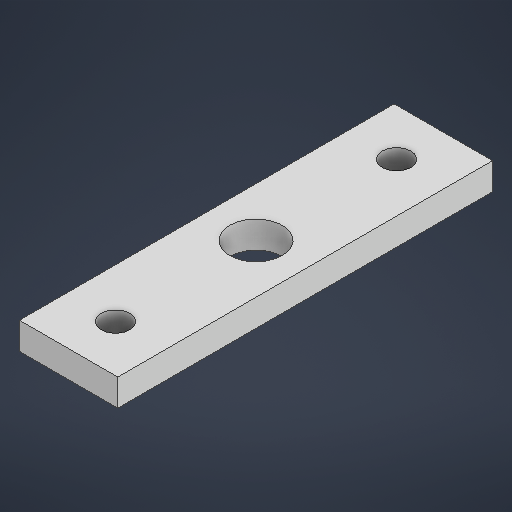
# Autodesk Inventor part: motor_hider_housing
Saved by Autodesk Inventor 2027.1 (Build 311270010, 270A)
## iProperties
Created: 2026-10-04
Part Number: motor_hider_housing
Material: Generic
Document SubType Name: Modeling
Designer: khaar
Density: 1 g/cm^3
Appearance: Default
Author: khaar
Autodesk Inventor part; units mm, degrees
ref_plane "YZ Plane" through (0, 0, 0) normal (1, 0, 0) x (0, 1, 0)
ref_plane "XZ Plane" through (0, 0, 0) normal (0, 1, 0) x (-1, 0, 0)
ref_plane "XY Plane" through (0, 0, 0) normal (0, 0, 1) x (1, 0, 0)
sketch "Sketch1" plane through (0, 0, 0) normal (0, 1, 0) x (-1, 0, 0)
  line L0 (21, 80) -> (-21, 80)
  line L1 (-21, 80) -> (-21, -80)
  line L2 (-21, -80) -> (21, -80)
  line L3 (21, -80) -> (21, 80)
  line L4 (21, 80) -> (-21, -80) construction
  line L5 (-21, 80) -> (21, -80) construction
  point P0 (0, 0)
  dimension "d0" = 160
  dimension "d1" = 42
  constraints: 12 end point, 2 midpoint, 2 parallel, 1 horizontal, 1 perpendicular
  measures "d0" distance of L2.end L0.start
  measures "d1" distance of L1.end L2.end
extrude "Extrusion1" add sketch "Sketch1" along normal blind 11.5
sketch "Sketch2" plane through (0, 11.5, 0) normal (0, 1, 0) x (1, 0, 0)
  circle A0 centre (0, 0) radius 11.2
  circle A1 centre (0, 60) radius 6.1
  circle A2 centre (0, -60) radius 6.1
  dimension "d4" = 22.4
  dimension "d5" = 12.2
  dimension "d6" = 12.2
  dimension "d7" = 60
  dimension "d8" = 60
  constraints: 3 centre point, 1 coincident
  measures "d4" diameter of A0
  measures "d5" diameter of A1
  measures "d6" diameter of A2
  measures "d7" distance of A1.centre point (0, 0)
  measures "d8" distance of point (0, 0) A2.centre
extrude "Extrusion2" cut sketch "Sketch2" against normal blind 12.2
equation "\"d9\" = d6"
body "Solid1"
